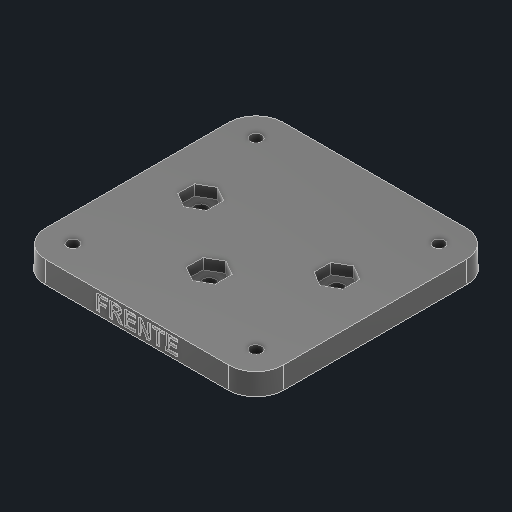
# Autodesk Inventor part: Suporte lidar
Saved by Autodesk Inventor 2026.1 (Build 301233000, 233)
## iProperties
Created: 2025-03-16
Part Number: Suporte lidar
Material: Plástico PC/ABS
Document SubType Name: Modeling
Designer: Cliente
Density: 0.824531 g/cm^3
Appearance: Suave - Preto
Mass: 12.37 g
Surface Area: 76.4221 cm^2
Volume: 15.0025 cm^3
Author: Cliente
Autodesk Inventor part; units mm, degrees
ref_plane "YZ Plane" through (0, 0, 0) normal (1, 0, 0) x (0, 1, 0)
ref_plane "XY Plane" through (0, 0, 0) normal (0, 0, 1) x (1, 0, 0)
sketch "Esboço1" plane through (0, 0, 0) normal (0, 1, 0) x (-1, 0, 0)
  line L0 (-27.9, 27.9) -> (27.9, 27.9)
  line L1 (27.9, 27.9) -> (27.9, -27.9)
  line L2 (27.9, -27.9) -> (-27.9, -27.9)
  line L3 (-27.9, -27.9) -> (-27.9, 27.9)
  line L4 (-27.9, 27.9) -> (27.9, -27.9) construction
  line L5 (27.9, 27.9) -> (-27.9, -27.9) construction
  line L6 (-21.5, -21.5) -> (21.5, -21.5)
  line L7 (21.5, -21.5) -> (21.5, 21.5)
  line L8 (21.5, 21.5) -> (-21.5, 21.5)
  line L9 (-21.5, 21.5) -> (-21.5, -21.5)
  line L10 (-21.5, -21.5) -> (21.5, 21.5) construction
  line L11 (21.5, -21.5) -> (-21.5, 21.5) construction
  arc A0 (-27.9, -21.5) -> (-21.5, -27.9) centre (-21.5, -21.5) ccw
  arc A1 (-21.5, 27.9) -> (-27.9, 21.5) centre (-21.5, 21.5) ccw
  arc A2 (27.9, 21.5) -> (21.5, 27.9) centre (21.5, 21.5) ccw
  arc A3 (21.5, -27.9) -> (27.9, -21.5) centre (21.5, -21.5) ccw
  point P0 (0, 0)
  dimension "d0" = 55.8
  dimension "d1" = 55.8
  dimension "d2" = 43
  dimension "d3" = 43
  constraints: 24 end point, 8 point on circle, 8 point on line, 4 centre point, 4 midpoint, 4 parallel, 4 tangent, 3 coincident, 2 horizontal, 2 perpendicular
  measures "d0" distance of L1.end L2.end
  measures "d1" distance of L0.end L1.end
  measures "d2" distance of L8.end L7.end
  measures "d3" distance of L7.end L6.end
ref_plane "Plano de trabalho1" through (0, -23.1, 0) normal (0, 1, 0) x (-1, 0, 0)
sketch "Esboço2" plane through (0, -23.1, 0) normal (0, 1, 0) x (-1, 0, 0)
  line L0 (-28.75, -28.75) -> (28.75, -28.75)
  line L1 (28.75, -28.75) -> (28.75, 28.75)
  line L2 (28.75, 28.75) -> (-28.75, 28.75)
  line L3 (-28.75, 28.75) -> (-28.75, -28.75)
  line L4 (-28.75, -28.75) -> (28.75, 28.75) construction
  line L5 (28.75, -28.75) -> (-28.75, 28.75) construction
  line L6 (-21.5, -21.5) -> (21.5, -21.5)
  line L7 (21.5, -21.5) -> (21.5, 21.5)
  line L8 (21.5, 21.5) -> (-21.5, 21.5)
  line L9 (-21.5, 21.5) -> (-21.5, -21.5)
  line L10 (-21.5, -21.5) -> (21.5, 21.5) construction
  line L11 (21.5, -21.5) -> (-21.5, 21.5) construction
  arc A0 (28.75, 21.5) -> (21.5, 28.75) centre (21.5, 21.5) ccw
  arc A1 (21.5, -28.75) -> (28.75, -21.5) centre (21.5, -21.5) ccw
  arc A2 (-21.5, 28.75) -> (-28.75, 21.5) centre (-21.5, 21.5) ccw
  arc A3 (-28.75, -21.5) -> (-21.5, -28.75) centre (-21.5, -21.5) ccw
  point P0 (0, 0)
  dimension "d5" = 57.5
  dimension "d6" = 57.5
  dimension "d7" = 43
  dimension "d8" = 43
  constraints: 24 end point, 8 point on circle, 8 point on line, 4 centre point, 4 coincident, 4 midpoint, 4 parallel, 4 tangent, 2 horizontal, 2 perpendicular
  measures "d5" distance of L2.end L1.end
  measures "d6" distance of L1.end L0.end
  measures "d7" distance of L8.end L7.end
  measures "d8" distance of L7.end L6.end
loft "Transição1" add profiles "Esboço2", "Esboço1" contours A3 L3 A2 L2 A0 L1 A1 L0 | L9 L8 L7 L6 / L0 A2 L1 A3 L2 A0 L3 A1 | L9 L8 L7 L6
sketch "Esboço3" plane through (-21.5, -23.1, 28.75) normal (0, -1, 0) x (1, 0, 0)
  line L0 (0, 0) -> (43, 0) projected
  arc A0 (0, 0) -> (-7.25, -7.25) centre (0, -7.25) ccw projected
  line L1 (-7.25, -50.25) -> (-7.25, -7.25) projected
  arc A1 (-7.25, -50.25) -> (0, -57.5) centre (0, -50.25) ccw projected
  line L2 (43, -57.5) -> (0, -57.5) projected
  arc A2 (43, -57.5) -> (50.25, -50.25) centre (43, -50.25) ccw projected
  line L3 (50.25, -7.25) -> (50.25, -50.25) projected
  arc A3 (50.25, -7.25) -> (43, 0) centre (43, -7.25) ccw projected
  point P0 (21.5, -28.75)
extrude "Extrusão1" cut sketch "Esboço3" against normal blind 18.1
sketch "Esboço4" plane through (-21.5, -5, 28.75) normal (0, -1, 0) x (1, 0, 0)
  line L0 (0, -0.666) -> (43, -0.666) projected
  arc A0 (0, -0.666) -> (-6.584, -7.25) centre (0, -7.25) ccw projected
  line L1 (-6.584, -50.25) -> (-6.584, -7.25) projected
  arc A1 (-6.584, -50.25) -> (0, -56.834) centre (0, -50.25) ccw projected
  line L2 (43, -56.834) -> (0, -56.834) projected
  arc A2 (43, -56.834) -> (49.584, -50.25) centre (43, -50.25) ccw projected
  line L3 (49.584, -7.25) -> (49.584, -50.25) projected
  arc A3 (49.584, -7.25) -> (43, -0.666) centre (43, -7.25) ccw projected
  circle A4 centre (0, -7.25) radius 1.35
  circle A5 centre (43, -7.25) radius 1.35
  circle A6 centre (43, -50.25) radius 1.35
  circle A7 centre (0, -50.25) radius 1.35
  point P0 (21.5, -28.75)
  dimension "d15" = 2.7
  dimension "d16" = 2.7
  dimension "d17" = 2.7
  dimension "d18" = 2.7
  constraints: 4 centre point, 4 coincident
  measures "d15" diameter of A4
  measures "d16" diameter of A5
  measures "d17" diameter of A6
  measures "d18" diameter of A7
extrude "Extrusão2" cut sketch "Esboço4" against normal through all contours A4 | A5 | A6 | A7
sketch "Esboço5" plane through (-21.5, 0, 27.9) normal (0, 1, 0) x (1, 0, 0)
  line L0 (18.9, 29.85) -> (24.1, 29.85)
  line L1 (24.1, 29.85) -> (24.1, 25.95)
  line L2 (24.1, 25.95) -> (18.9, 25.95)
  line L3 (18.9, 25.95) -> (18.9, 29.85)
  line L4 (18.9, 29.85) -> (24.1, 25.95) construction
  line L5 (24.1, 29.85) -> (18.9, 25.95) construction
  line L6 (32, 21.9) -> (11, 21.9)
  line L7 (11, 21.9) -> (11, 33.9)
  line L8 (11, 33.9) -> (32, 33.9)
  line L9 (32, 33.9) -> (32, 21.9)
  line L10 (32, 21.9) -> (11, 33.9) construction
  line L11 (11, 21.9) -> (32, 33.9) construction
  circle A0 centre (37.5, 30.9) radius 1.55
  circle A1 centre (5.5, 30.9) radius 1.55
  circle A2 centre (21.5, 16.9) radius 1.55
  line L12 (37.5, 26.974) -> (34.1, 28.937)
  line L13 (34.1, 28.937) -> (34.1, 32.863)
  line L14 (34.1, 32.863) -> (37.5, 34.826)
  line L15 (37.5, 34.826) -> (40.9, 32.863)
  line L16 (40.9, 32.863) -> (40.9, 28.937)
  line L17 (40.9, 28.937) -> (37.5, 26.974)
  line L18 (5.5, 26.974) -> (2.1, 28.937)
  line L19 (2.1, 28.937) -> (2.1, 32.863)
  line L20 (2.1, 32.863) -> (5.5, 34.826)
  line L21 (5.5, 34.826) -> (8.9, 32.863)
  line L22 (8.9, 32.863) -> (8.9, 28.937)
  line L23 (8.9, 28.937) -> (5.5, 26.974)
  line L24 (21.5, 12.974) -> (18.1, 14.937)
  line L25 (18.1, 14.937) -> (18.1, 18.863)
  line L26 (18.1, 18.863) -> (21.5, 20.826)
  line L27 (21.5, 20.826) -> (24.9, 18.863)
  line L28 (24.9, 18.863) -> (24.9, 14.937)
  line L29 (24.9, 14.937) -> (21.5, 12.974)
  point P0 (21.5, 27.9)
  point P1 (21.5, 27.9)
  point P2 (21.5, 27.9)
  point P3 (21.5, 27.9)
  dimension "d21" = 5.2
  dimension "d22" = 3.9
  dimension "d23" = 21
  dimension "d24" = 12
  dimension "d25" = 3.1
  dimension "d26" = 3.1
  dimension "d27" = -16
  dimension "d28" = -16
  dimension "d29" = -3
  dimension "d30" = 3.1
  dimension "d31" = 11
  dimension "d34" = 6.8
  dimension "d35" = 6.8
  dimension "d36" = 6.8
  constraints: 60 end point, 4 coincident, 4 midpoint, 4 parallel, 4 vertical alignment, 3 centre point, 2 horizontal, 2 perpendicular, 1 horizontal alignment, 39 other
  measures "d21" distance of L1.end L2.end
  measures "d22" distance of L0.end L1.end
  measures "d23" distance of L7.end L8.end
  measures "d24" distance of L6.end L7.end
  measures "d25" diameter of A0
  measures "d26" diameter of A1
  measures "d27" horizontal distance of A1.centre point (21.5, 27.9)
  measures "d28" horizontal distance of point (21.5, 27.9) A0.centre
  measures "d29" vertical distance of A0.centre point (21.5, 27.9)
  measures "d30" diameter of A2
  measures "d31" distance of point (21.5, 27.9) A2.centre
  measures "d34" distance between parallel lines of L25 L28
  measures "d35" distance between parallel lines of L16 L13
  measures "d36" distance between parallel lines of L19 L22
extrude "Extrusão3" cut sketch "Esboço5" against normal through all contours A0 | A1 | A2
extrude "Extrusão4" cut sketch "Esboço5" against normal blind 2.5 contours L12 L13 L14 L15 L16 L17 | L18 L19 L20 L21 L22 L23 | L24 L25 L26 L27 L28 L29
sketch "Esboço6" plane through (-21.5, 0, 27.9) normal (0, 0.0368, 0.9993) x (1, 0, 0)
  line L0 (17.9145, -0.7517) -> (25.0855, -0.7517) construction
  line L1 (25.0855, -0.7517) -> (25.0855, -4.2517) construction
  line L2 (25.0855, -4.2517) -> (17.9145, -4.2517) construction
  line L3 (17.9145, -4.2517) -> (17.9145, -0.7517) construction
  line L4 (0, -5.0034) -> (43, -5.0034) projected
  line L5 (43, 0) -> (43, -5.0034) projected
  line L6 (0, 0) -> (43, 0) projected
  line L7 (0, -5.0034) -> (0, 0) projected
  line L8 (12.0751, -4.2517) -> (12.0751, -0.7517)
  line L9 (12.0751, -0.7517) -> (14.4787, -0.7517)
  line L10 (14.4787, -0.7517) -> (14.4787, -1.3439)
  line L11 (14.4787, -1.3439) -> (12.782, -1.3439)
  line L12 (12.782, -1.3439) -> (12.782, -2.1709)
  line L13 (12.782, -2.1709) -> (14.2466, -2.1709)
  line L14 (14.2466, -2.1709) -> (14.2466, -2.7631)
  line L15 (14.2466, -2.7631) -> (12.782, -2.7631)
  line L16 (12.782, -2.7631) -> (12.782, -4.2517)
  line L17 (12.782, -4.2517) -> (12.0751, -4.2517)
  line L18 (15.0629, -4.2517) -> (15.0629, -0.7517)
  line L19 (15.0629, -0.7517) -> (16.5514, -0.7517)
  spline S0 degree 2 poles (16.5514, -0.7517) (17.1143, -0.7517) (17.6212, -0.9411) (17.928, -1.4213) (17.928, -1.7334) knots 0 0 0 1 2 3 3 3
  spline S1 degree 2 poles (17.928, -1.7334) (17.928, -2.1255) (17.4665, -2.6404) (17.005, -2.7071) knots 0 0 0 1 2 2 2
  spline S2 degree 2 poles (17.005, -2.7071) (17.2344, -2.8405) (17.5332, -3.1606) (17.7866, -3.5688) knots 0 0 0 1 2 2 2
  line L20 (17.7866, -3.5688) -> (18.2134, -4.2517)
  line L21 (18.2134, -4.2517) -> (17.3678, -4.2517)
  line L22 (17.3678, -4.2517) -> (16.8582, -3.4887)
  spline S3 degree 2 poles (16.8582, -3.4887) (16.5835, -3.0806) (16.3834, -2.8672) (16.1593, -2.7898) (15.9139, -2.7898) knots 0 0 0 1 2 3 3 3
  line L23 (15.9139, -2.7898) -> (15.7698, -2.7898)
  line L24 (15.7698, -2.7898) -> (15.7698, -4.2517)
  line L25 (15.7698, -4.2517) -> (15.0629, -4.2517)
  line L26 (15.7698, -2.2323) -> (16.2927, -2.2323)
  spline S4 degree 2 poles (16.2927, -2.2323) (16.8022, -2.2323) (17.0556, -2.1469) (17.1997, -1.9361) (17.1997, -1.7787) knots 0 0 0 1 2 3 3 3
  spline S5 degree 2 poles (17.1997, -1.7787) (17.1997, -1.6027) (17.0103, -1.3839) (16.8396, -1.3546) knots 0 0 0 1 2 2 2
  spline S6 degree 2 poles (16.8396, -1.3546) (16.7515, -1.3439) (16.322, -1.3439) knots 0 0 0 1 1 1
  line L27 (16.322, -1.3439) -> (15.7698, -1.3439)
  line L28 (15.7698, -1.3439) -> (15.7698, -2.2323)
  line L29 (18.5949, -4.2517) -> (18.5949, -0.7517)
  line L30 (18.5949, -0.7517) -> (21.1905, -0.7517)
  line L31 (21.1905, -0.7517) -> (21.1905, -1.3439)
  line L32 (21.1905, -1.3439) -> (19.3018, -1.3439)
  line L33 (19.3018, -1.3439) -> (19.3018, -2.1202)
  line L34 (19.3018, -2.1202) -> (21.0598, -2.1202)
  line L35 (21.0598, -2.1202) -> (21.0598, -2.7124)
  line L36 (21.0598, -2.7124) -> (19.3018, -2.7124)
  line L37 (19.3018, -2.7124) -> (19.3018, -3.6595)
  line L38 (19.3018, -3.6595) -> (21.2572, -3.6595)
  line L39 (21.2572, -3.6595) -> (21.2572, -4.2517)
  line L40 (21.2572, -4.2517) -> (18.5949, -4.2517)
  line L41 (21.8628, -4.2517) -> (21.8628, -0.7517)
  line L42 (21.8628, -0.7517) -> (22.5484, -0.7517)
  line L43 (22.5484, -0.7517) -> (23.9863, -3.0993)
  line L44 (23.9863, -3.0993) -> (23.9863, -0.7517)
  line L45 (23.9863, -0.7517) -> (24.6399, -0.7517)
  line L46 (24.6399, -0.7517) -> (24.6399, -4.2517)
  line L47 (24.6399, -4.2517) -> (23.9329, -4.2517)
  line L48 (23.9329, -4.2517) -> (22.5164, -1.9548)
  line L49 (22.5164, -1.9548) -> (22.5164, -4.2517)
  line L50 (22.5164, -4.2517) -> (21.8628, -4.2517)
  line L51 (26.1764, -4.2517) -> (26.1764, -1.3439)
  line L52 (26.1764, -1.3439) -> (25.1387, -1.3439)
  line L53 (25.1387, -1.3439) -> (25.1387, -0.7517)
  line L54 (25.1387, -0.7517) -> (27.9184, -0.7517)
  line L55 (27.9184, -0.7517) -> (27.9184, -1.3439)
  line L56 (27.9184, -1.3439) -> (26.8834, -1.3439)
  line L57 (26.8834, -1.3439) -> (26.8834, -4.2517)
  line L58 (26.8834, -4.2517) -> (26.1764, -4.2517)
  line L59 (28.3773, -4.2517) -> (28.3773, -0.7517)
  line L60 (28.3773, -0.7517) -> (30.9729, -0.7517)
  line L61 (30.9729, -0.7517) -> (30.9729, -1.3439)
  line L62 (30.9729, -1.3439) -> (29.0842, -1.3439)
  line L63 (29.0842, -1.3439) -> (29.0842, -2.1202)
  line L64 (29.0842, -2.1202) -> (30.8422, -2.1202)
  line L65 (30.8422, -2.1202) -> (30.8422, -2.7124)
  line L66 (30.8422, -2.7124) -> (29.0842, -2.7124)
  line L67 (29.0842, -2.7124) -> (29.0842, -3.6595)
  line L68 (29.0842, -3.6595) -> (31.0396, -3.6595)
  line L69 (31.0396, -3.6595) -> (31.0396, -4.2517)
  line L70 (31.0396, -4.2517) -> (28.3773, -4.2517)
  point P0 (21.5, 1.0259)
  point P1 (17.9145, -2.5017)
  point P2 (0, -2.5017)
  point P3 (21.5, -0.7517)
  point P4 (21.5, 0)
  constraints: 4 midpoint, 1 horizontal alignment, 1 vertical alignment, 2 other
extrude "Extrusão5" cut sketch "Esboço6" against normal blind 0.5 contours L8 L9 L10 L11 L12 L13 L14 L15 L16 L17 | L18 L19 S0 S1 S2 L20 L21 L22 S3 L23 L24 L25 | L29 L30 L31 L32 L33 L34 L35 L36 L37 L38 L39 L40 | L41 L42 L43 L44 L45 L46 L47 L48 L49 L50 | L51 L52 L53 L54 L55 L56 L57 L58 | L59 L60 L61 L62 L63 L64 L65 L66 L67 L68 L69 L70
